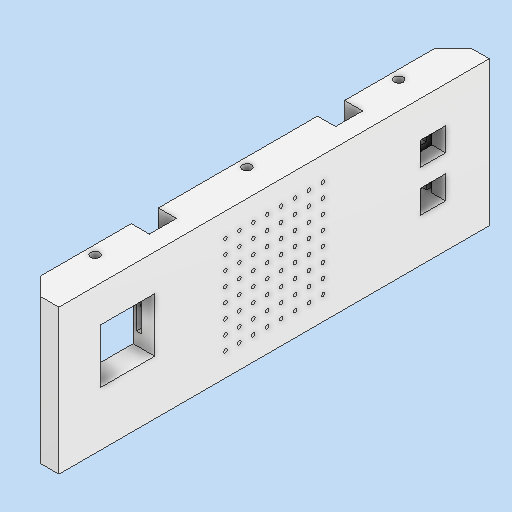
# Autodesk Inventor part: Pared_puertos
Saved by Autodesk Inventor 2027 (Build 310192000, 192)
## iProperties
Created: 2026-11-02
Part Number: Pared_puertos
Material: Plástico PBT
Document SubType Name: Modeling
Designer: alex
Density: 1.31 g/cm^3
Appearance: Suave - Blanco
Author: alex
Autodesk Inventor part; units mm, degrees
ref_plane "YZ Plane" through (0, 0, 0) normal (1, 0, 0) x (0, 1, 0)
ref_plane "XZ Plane" through (0, 0, 0) normal (0, 1, 0) x (-1, 0, 0)
ref_plane "XY Plane" through (0, 0, 0) normal (0, 0, 1) x (1, 0, 0)
sketch "Boceto1" plane through (0, 0, 0) normal (0, 1, 0) x (-1, 0, 0)
  arc A0 (-27.0444, 119.7007) -> (-22.0444, 124.7007) centre (-27.0444, 124.7007) ccw
  circle A1 centre (-27.0444, 124.7007) radius 2.5
  line L0 (-32.0444, 119.7007) -> (-27.0444, 119.7007)
  arc A2 (-27.0444, 119.7007) -> (-22.0444, 124.7007) centre (-27.0444, 124.7007) ccw
  line L1 (-22.0444, 129.7007) -> (-22.0444, 124.7007)
  line L2 (-22.0444, 124.7007) -> (-22.0444, 129.7007)
  line L3 (-22.0444, 129.7007) -> (215.9556, 129.7007)
  line L4 (215.9556, 129.7007) -> (215.9556, 124.7007)
  arc A3 (215.9556, 124.7007) -> (220.9556, 119.7007) centre (220.9556, 124.7007) ccw
  line L5 (225.9556, 119.7007) -> (225.9556, -33.2993)
  line L6 (220.9556, 119.7007) -> (225.9556, 119.7007)
  line L7 (225.9556, -123.2993) -> (225.9556, -118.2993)
  line L8 (225.9556, 119.7007) -> (225.9556, -118.2993)
  line L9 (225.9556, -118.2993) -> (220.9556, -118.2993)
  arc A4 (220.9556, -118.2993) -> (215.9556, -123.2993) centre (220.9556, -123.2993) ccw
  line L10 (-22.0444, -128.2993) -> (215.9556, -128.2993)
  line L11 (215.9556, -123.2993) -> (215.9556, -128.2993)
  line L12 (-22.0444, -128.2993) -> (-22.0444, -123.2993)
  line L13 (215.9556, -128.2993) -> (-22.0444, -128.2993)
  line L14 (-22.0444, -128.2993) -> (-22.0444, -123.2993)
  line L15 (-32.0444, -118.2993) -> (-32.0444, 119.7007)
  arc A5 (220.9556, -118.2993) -> (215.9556, -123.2993) centre (220.9556, -123.2993) ccw
  arc A6 (-22.0444, -123.2993) -> (-27.0444, -118.2993) centre (-27.0444, -123.2993) ccw
  arc A7 (-22.0444, -123.2993) -> (-27.0444, -118.2993) centre (-27.0444, -123.2993) ccw
  line L16 (-27.0444, -118.2993) -> (-32.0444, -118.2993)
  line L17 (-27.0444, -118.2993) -> (-32.0444, -118.2993)
  line L18 (-32.0444, 119.7007) -> (-22.0444, 119.7007)
  line L19 (-22.0444, 119.7007) -> (-22.0444, -118.2993)
  line L20 (-22.0444, -118.2993) -> (-32.0444, -118.2993)
  line L21 (-32.0444, -118.2993) -> (-32.0444, 119.7007)
  line L22 (-22.0444, 119.7007) -> (-12.0444, 119.7007)
  line L23 (-12.0444, 119.7007) -> (-12.0444, 109.7007)
  line L24 (-12.0444, 109.7007) -> (-22.0444, 109.7007)
  line L25 (-22.0444, 109.7007) -> (-22.0444, 119.7007)
  line L26 (-22.0444, -118.2993) -> (-12.0444, -118.2993)
  line L27 (-12.0444, -118.2993) -> (-12.0444, -108.2993)
  line L28 (-12.0444, -108.2993) -> (-22.0444, -108.2993)
  line L29 (-22.0444, -108.2993) -> (-22.0444, -118.2993)
  line L30 (-22.0444, 119.7007) -> (-12.0444, 109.7007)
  line L31 (-12.0444, 109.7007) -> (-22.0444, 109.7007)
  line L32 (-22.0444, 109.7007) -> (-22.0444, 59.7007)
  line L33 (-22.0444, 59.7007) -> (-12.0444, 59.7007)
  line L34 (-12.0444, 59.7007) -> (-12.0444, 109.7007)
  line L35 (-12.0444, -108.2993) -> (-22.0444, -108.2993)
  line L36 (-22.0444, -108.2993) -> (-22.0444, -58.2993)
  line L37 (-22.0444, -58.2993) -> (-12.0444, -58.2993)
  line L38 (-12.0444, -58.2993) -> (-12.0444, -108.2993)
  line L39 (-22.0444, -118.2993) -> (-12.0444, -108.2993)
  line L40 (-22.0444, 44.7007) -> (-12.0444, 44.7007)
  line L41 (-12.0444, 44.7007) -> (-12.0444, -43.2993)
  line L42 (-12.0444, -43.2993) -> (-22.0444, -43.2993)
  line L43 (-22.0444, -43.2993) -> (-22.0444, 44.7007)
  circle A8 centre (-17.0444, 84.7007) radius 2.5
  circle A9 centre (-17.0444, -83.2993) radius 2.5
  circle A10 centre (-17.0444, 0.7007) radius 2.5
  point P0 (0, 0)
  point P1 (-229.0444, 129.7007)
  dimension "d0" = 10
  dimension "d1" = 10
  dimension "d2" = 10
  dimension "d3" = 10
  dimension "d4" = 50
  dimension "d5" = 50
  dimension "d6" = 15
  dimension "d7" = 15
  dimension "d8" = 5
  dimension "d9" = 5
  dimension "d10" = 25
  dimension "d11" = 25
  dimension "d12" = 5
  constraints: 88 end point, 14 point on circle, 13 parallel, 13 perpendicular, 11 centre point, 7 horizontal, 5 point on line, 2 concentric, 1 coincident, 1 collinear, 1 vertical
  measures "d0" distance of L23.end L24.end
  measures "d1" distance of L22.end L23.end
  measures "d2" distance of L28.end L27.end
  measures "d3" distance of L27.end L26.end
  measures "d4" distance of L32.end L31.end
  measures "d5" distance of L35.end L36.end
  measures "d6" distance between parallel lines of L33 L40
  measures "d7" distance between parallel lines of L42 L37
  measures "d8" diameter of A8
  measures "d9" diameter of A9
  measures "d10" distance from line of L33 A8.centre
  measures "d11" distance from line of A9.centre L37
  measures "d12" diameter of A10
extrude "Extrusión1" add sketch "Boceto1" along normal blind 80 contours L18 L19 L20 L16 L15 L0 | L30 L24 L19 | L24 L34 L33 L19 | L19 L28 L39 | L40 L41 L42 L19 | L19 L37 L38 L28
sketch "Boceto2" plane through (32.0444, 0, 119.7007) normal (1, 0, 0) x (0, 0, -1)
  line L0 (23, 60) -> (53, 60)
  line L1 (53, 60) -> (53, 30)
  line L2 (53, 30) -> (23, 30)
  line L3 (23, 30) -> (23, 60)
  line L4 (0, 80) -> (238, 80) projected
  line L5 (0, 0) -> (0, 80) projected
  line L6 (199.856, 60) -> (213.856, 60)
  line L7 (213.856, 60) -> (213.856, 47)
  line L8 (213.856, 47) -> (199.856, 47)
  line L9 (199.856, 47) -> (199.856, 60)
  line L10 (199.856, 37) -> (213.856, 37)
  line L11 (213.856, 37) -> (213.856, 24)
  line L12 (213.856, 24) -> (199.856, 24)
  line L13 (199.856, 24) -> (199.856, 37)
  point P0 (119.7007, 0)
  dimension "d15" = 30
  dimension "d16" = 30
  dimension "d17" = 20
  dimension "d18" = 23
  dimension "d19" = 14
  dimension "d20" = 13
  dimension "d21" = 20
  dimension "d22" = 13
  dimension "d23" = 10
  constraints: 24 end point, 6 parallel, 3 horizontal, 3 perpendicular
  measures "d15" distance of L1.end L2.end
  measures "d16" distance of L0.end L1.end
  measures "d17" distance between parallel lines of L4 L0
  measures "d18" distance between parallel lines of L5 L3
  measures "d19" distance of L7.end L8.end
  measures "d20" distance of L6.end L7.end
  measures "d21" distance between parallel lines of L4 L6
  measures "d22" distance of L10.end L11.end
  measures "d23" distance between parallel lines of L10 L8
extrude "Extrusión2" cut sketch "Boceto2" against normal blind 80
sketch "Boceto3" plane through (12.0444, 0, -108.2993) normal (-1, 0, 0) x (0, 0, 1)
  point P0 (108.2993, 0)
sketch "Boceto4" plane through (12.0444, 0, -108.2993) normal (-1, 0, 0) x (0, 0, 1)
  line L0 (0, 0) -> (0, 80) projected
  line L1 (218, 0) -> (218, 80) projected
  line L2 (0, 70) -> (218, 70)
  line L3 (218, 70) -> (218, 10)
  line L4 (218, 10) -> (0, 10)
  line L5 (0, 10) -> (0, 70)
  line L6 (0, 0) -> (50, 0) projected
  line L7 (0, 80) -> (50, 80) projected
  point P0 (108.2993, 0)
  point P1 (0, 10)
  dimension "d26" = 10
  dimension "d27" = 10
  constraints: 8 end point, 2 parallel, 2 point on line, 1 horizontal, 1 perpendicular
  measures "d26" distance between parallel lines of L6 L4
  measures "d27" distance between parallel lines of L2 L7
extrude "Extrusión3" cut sketch "Boceto4" against normal blind 15
sketch "Boceto5" plane through (27.0444, 0, -108.2993) normal (-1, 0, 0) x (0, 0, 1)
  line L0 (8.144, 65) -> (34.144, 65)
  line L1 (34.144, 65) -> (34.144, 42)
  line L2 (34.144, 42) -> (8.144, 42)
  line L3 (8.144, 42) -> (8.144, 65)
  line L4 (28.144, 47) -> (28.144, 60) projected
  line L5 (14.144, 60) -> (14.144, 47) projected
  line L6 (28.144, 60) -> (14.144, 60) projected
  line L7 (14.144, 47) -> (28.144, 47) projected
  line L8 (8.144, 42) -> (34.144, 42)
  line L9 (34.144, 42) -> (34.144, 19)
  line L10 (34.144, 19) -> (8.144, 19)
  line L11 (8.144, 19) -> (8.144, 42)
  line L12 (28.144, 24) -> (28.144, 37) projected
  line L13 (14.144, 37) -> (14.144, 24) projected
  line L14 (28.144, 37) -> (14.144, 37) projected
  line L15 (14.144, 24) -> (28.144, 24) projected
  circle A0 centre (11.144, 53.5) radius 1.5
  circle A1 centre (11.144, 30.5) radius 1.5
  circle A2 centre (31.144, 30.5) radius 1.5
  circle A3 centre (31.144, 53.5) radius 1.5
  point P0 (108.2993, 0)
  point P1 (21.144, 47)
  point P2 (8.144, 42)
  dimension "d30" = 6
  dimension "d31" = 6
  dimension "d32" = 5
  dimension "d33" = 5
  dimension "d34" = 6
  dimension "d35" = 6
  dimension "d36" = 5
  dimension "d37" = 5
  dimension "d38" = 3
  dimension "d39" = 6.5
  dimension "d40" = 3
  dimension "d41" = 3
  dimension "d42" = 6.5
  dimension "d43" = 3
  dimension "d44" = 3
  dimension "d45" = 3
  constraints: 16 end point, 4 centre point, 4 parallel, 2 coincident, 2 horizontal, 2 perpendicular, 1 midpoint
  measures "d30" distance between parallel lines of L4 L1
  measures "d31" distance between parallel lines of L3 L5
  measures "d32" distance between parallel lines of L6 L0
  measures "d33" distance from line of L2 point (21.144, 47)
  measures "d34" distance between parallel lines of L12 L9
  measures "d35" distance between parallel lines of L11 L13
  measures "d36" distance between parallel lines of L14 L8
  measures "d37" distance between parallel lines of L10 L15
  measures "d38" distance from line of L5 point (11.144, 53.5)
  measures "d39" distance from line of point (11.144, 53.5) L6
  measures "d40" diameter of A0
  measures "d41" distance from line of L4 point (31.144, 53.5)
  measures "d42" distance from line of point (31.144, 53.5) L6
  measures "d43" diameter of A1
  measures "d44" diameter of A2
  measures "d45" diameter of A3
extrude "Extrusión4" add sketch "Boceto5" along normal blind 7.8
sketch "Boceto6" plane through (27.0444, 19, -74.1553) normal (0, 0, 1) x (1, 0, 0)
  line L0 (5, 41) -> (-7.8, 41) projected
  line L1 (5, 5) -> (-7.8, 5) projected
  line L2 (-5.5162, 41) -> (-2.5162, 41)
  line L3 (-2.5162, 41) -> (-2.5162, 5)
  line L4 (-2.5162, 5) -> (-5.5162, 5)
  line L5 (-5.5162, 5) -> (-5.5162, 41)
  point P0 (-27.0444, -19)
  point P1 (-2.5162, 41)
  dimension "d48" = 3
  constraints: 8 end point, 2 parallel, 2 point on line, 1 horizontal, 1 perpendicular
  measures "d48" distance of L3.end L4.end
extrude "Extrusión5" cut sketch "Boceto6" against normal blind 29.7
sketch "Boceto7" plane through (27.0444, 0, -108.2993) normal (-1, 0, 0) x (0, 0, 1)
  line L0 (169, 63.1359) -> (211, 63.1359)
  line L1 (211, 63.1359) -> (211, 25.0492)
  line L2 (211, 25.0492) -> (169, 25.0492)
  line L3 (169, 25.0492) -> (169, 63.1359)
  line L4 (205, 30) -> (205, 60) projected
  line L5 (175, 60) -> (175, 30) projected
  line L6 (171.5, 63) -> (208.5, 63)
  line L7 (208.5, 63) -> (208.5, 28.5687)
  line L8 (208.5, 28.5687) -> (171.5, 28.5687)
  line L9 (171.5, 28.5687) -> (171.5, 63)
  line L10 (208.5, 60) -> (208.5, 48.34)
  line L11 (171.5, 63) -> (171.5, 48.34)
  circle A0 centre (171.5, 48.34) radius 1.5
  circle A1 centre (208.5, 48.34) radius 1.5
  line L12 (171.5, 48.34) -> (171.5, 45.84)
  line L13 (171.5, 48.34) -> (171.5, 50.84)
  line L14 (208.5, 48.34) -> (208.5, 50.84)
  line L15 (208.5, 48.34) -> (208.5, 45.84)
  arc A2 (208.5, 45.84) -> (208.5, 50.84) centre (208.5, 48.34) ccw
  arc A3 (171.5, 50.84) -> (171.5, 45.84) centre (171.5, 48.34) ccw
  line L16 (205, 60) -> (175, 60) projected
  point P0 (108.2993, 0)
  point P1 (190, 63)
  point P2 (190, 60)
  point P3 (208.5, 50.84)
  dimension "d51" = 6
  dimension "d52" = 6
  dimension "d53" = 3.5
  dimension "d54" = 3.5
  dimension "d55" = 11.66
  dimension "d56" = 14.66
  dimension "d57" = 3
  dimension "d58" = 3
  dimension "d59" = 2.5
  dimension "d60" = 2.5
  dimension "d61" = 2.5
  dimension "d62" = 2.5
  dimension "d63" = 3
  constraints: 28 end point, 7 point on line, 4 centre point, 4 parallel, 4 point on circle, 2 coincident, 2 horizontal, 2 midpoint, 2 perpendicular, 2 tangent
  measures "d51" distance between parallel lines of L4 L1
  measures "d52" distance between parallel lines of L3 L5
  measures "d53" distance between parallel lines of L4 L7
  measures "d54" distance between parallel lines of L9 L5
  measures "d55" distance of L10.start L10.end
  measures "d56" distance of L6.start L11.end
  measures "d57" diameter of A0
  measures "d58" diameter of A1
  measures "d59" distance of L12.start L12.end
  measures "d60" distance of L12.start L13.end
  measures "d61" distance of L14.start L14.end
  measures "d62" distance of L14.start L15.end
  measures "d63" distance of point (190, 63) point (190, 60)
extrude "Extrusión6" add sketch "Boceto7" along normal blind 7 contours A3 L9 A0 | A2 L7 A1 | L9 L6 L7 A1 L8 A0
sketch "Boceto8" plane through (20.0444, 0, -108.2993) normal (-1, 0, 0) x (0, 0, 1)
  line L0 (205, 30) -> (205, 60) projected
  line L1 (175, 60) -> (205, 60)
  line L2 (205, 60) -> (205, 30)
  line L3 (205, 30) -> (175, 30)
  line L4 (175, 30) -> (175, 60)
  point P0 (108.2993, 0)
  constraints: 8 end point, 2 parallel, 1 horizontal, 1 perpendicular
extrude "Extrusión7" cut sketch "Boceto8" against normal blind 7
sketch "Boceto9" plane through (27.0444, 50.84, 63.2007) normal (0, 0, -1) x (-1, 0, 0)
  line L0 (2.5588, 4.5741) -> (5.1212, 4.5741)
  line L1 (5.1212, 4.5741) -> (5.1212, -13.7755)
  line L2 (5.1212, -13.7755) -> (2.5588, -13.7755)
  line L3 (2.5588, -13.7755) -> (2.5588, 4.5741)
  point P0 (27.0444, -50.84)
  constraints: 8 end point, 2 parallel, 1 horizontal, 1 perpendicular
extrude "Extrusión8" cut sketch "Boceto9" against normal blind 47
sketch "Boceto10" plane through (32.0444, 30, 96.7007) normal (0, 0, -1) x (-1, 0, 0)
  line L0 (7.5588, 25.4141) -> (10.1212, 25.4141) projected
  line L1 (10.1212, 25.4141) -> (10.1212, 7.0645) projected
  line L2 (7.5588, 25.4141) -> (10.1212, 25.4141)
  line L3 (10.1212, 25.4141) -> (10.1212, 7.0645)
  line L4 (10.1212, 7.0645) -> (7.5588, 7.0645)
  line L5 (7.5588, 7.0645) -> (7.5588, 25.4141)
  point P0 (32.0444, -30)
  constraints: 8 end point, 2 parallel, 1 horizontal, 1 perpendicular
extrude "Extrusión9" cut sketch "Boceto10" along normal blind 47
sketch "Boceto11" plane through (27.0444, 0, -108.2993) normal (-1, 0, 0) x (0, 0, 1)
  line L0 (85, 64) -> (133, 64)
  line L1 (133, 64) -> (133, 16)
  line L2 (133, 16) -> (85, 16)
  line L3 (85, 16) -> (85, 64)
  line L4 (0, 70) -> (218, 70) projected
  line L5 (109, 70) -> (109, 10)
  line L6 (218, 10) -> (0, 10) projected
  line L7 (228, 0) -> (228, 80) projected
  line L8 (228, 40) -> (-10, 40)
  line L9 (-10, 0) -> (-10, 80) projected
  line L10 (88, 61) -> (130, 61)
  line L11 (130, 61) -> (130, 19)
  line L12 (130, 19) -> (88, 19)
  line L13 (88, 19) -> (88, 61)
  point P0 (108.2993, 0)
  dimension "d72" = 48
  dimension "d73" = 48
  dimension "d74" = 24
  dimension "d75" = 24
  dimension "d76" = 3
  dimension "d77" = 3
  dimension "d78" = 3
  dimension "d79" = 3
  constraints: 20 end point, 4 midpoint, 4 parallel, 2 horizontal, 2 perpendicular
  measures "d72" distance of L1.end L2.end
  measures "d73" distance of L0.end L1.end
  measures "d74" distance between parallel lines of L1 L5
  measures "d75" distance between parallel lines of L0 L8
  measures "d76" distance between parallel lines of L10 L0
  measures "d77" distance between parallel lines of L13 L3
  measures "d78" distance between parallel lines of L12 L2
  measures "d79" distance between parallel lines of L11 L1
extrude "Extrusión10" add sketch "Boceto11" along normal blind 10 contours L0 L5 L10 L13 L8 L3 | L0 L1 L8 L11 L10 L5 | L8 L13 L12 L5 L2 L3 | L1 L2 L5 L12 L11 L8
sketch "Boceto12" plane through (17.0444, 0, -108.2993) normal (-1, 0, 0) x (0, 0, 1)
  line L0 (88, 19) -> (88, 61) projected
  circle A0 centre (88, 40) radius 1.5
  line L1 (130, 61) -> (130, 19) projected
  circle A1 centre (130, 40) radius 1.5
  circle A2 centre (88, 40) radius 2
  circle A3 centre (130, 40) radius 2
  point P0 (108.2993, 0)
  point P1 (130, 41.5)
  point P2 (130, 38.5)
  point P3 (88, 41.5)
  point P4 (88, 38.5)
  dimension "d82" = 3
  dimension "d83" = 3
  dimension "d84" = 4
  dimension "d85" = 4
  constraints: 4 centre point, 2 coincident, 2 midpoint
  measures "d82" diameter of A0
  measures "d83" diameter of A1
  measures "d84" diameter of A2
  measures "d85" diameter of A3
extrude "Extrusión11" add sketch "Boceto12" against normal blind 2 contours A2 L0 A0 | L0 A0 A2 | A3 L1 A1 | L1 A1 A3
extrude "Extrusión12" cut sketch "Boceto12" against normal blind 2 contours A0 L0 | A1 L1 picked at (87.8803, 39.5145) picked at (130.5, 40)
sketch "Boceto13" plane through (27.0444, 16, 24.7007) normal (0, 0, 1) x (1, 0, 0)
  line L0 (-8, 19) -> (-5, 19)
  line L1 (-5, 19) -> (-5, 29)
  line L2 (-5, 29) -> (-8, 29)
  line L3 (-8, 29) -> (-8, 19)
  line L4 (-10, 0) -> (-10, 48) projected
  point P0 (-27.0444, -16)
  point P1 (-6.5, 19)
  point P2 (-10, 24)
  dimension "d90" = 3
  dimension "d91" = 10
  dimension "d92" = 5
  constraints: 8 end point, 2 midpoint, 2 parallel, 1 horizontal, 1 perpendicular
  measures "d90" distance of L2.end L1.end
  measures "d91" distance of L1.end L0.end
  measures "d92" vertical distance of point (-6.5, 19) point (-10, 24)
extrude "Extrusión13" cut sketch "Boceto13" against normal blind 57.5
sketch "Boceto14" plane through (32.0444, 0, 119.7007) normal (1, 0, 0) x (0, 0, -1)
  line L0 (146, 13) -> (92, 13)
  line L1 (146, 67) -> (146, 13)
  line L2 (95, 16) -> (143, 16) projected
  line L3 (143, 16) -> (143, 64) projected
  line L4 (95, 64) -> (95, 16) projected
  line L5 (143, 64) -> (95, 64) projected
  circle A0 centre (146, 13) radius 1
  circle A1 centre (146, 20.7) radius 1
  circle A2 centre (146, 28.4) radius 1
  circle A3 centre (146, 36.1) radius 1
  circle A4 centre (146, 43.8) radius 1
  circle A5 centre (146, 51.5) radius 1
  circle A6 centre (146, 59.2) radius 1
  circle A7 centre (146, 66.9) radius 1
  circle A8 centre (138.3, 13) radius 1
  circle A9 centre (138.3, 20.7) radius 1
  circle A10 centre (138.3, 28.4) radius 1
  circle A11 centre (138.3, 36.1) radius 1
  circle A12 centre (138.3, 43.8) radius 1
  circle A13 centre (138.3, 51.5) radius 1
  circle A14 centre (138.3, 59.2) radius 1
  circle A15 centre (138.3, 66.9) radius 1
  circle A16 centre (130.6, 13) radius 1
  circle A17 centre (130.6, 20.7) radius 1
  circle A18 centre (130.6, 28.4) radius 1
  circle A19 centre (130.6, 36.1) radius 1
  circle A20 centre (130.6, 43.8) radius 1
  circle A21 centre (130.6, 51.5) radius 1
  circle A22 centre (130.6, 59.2) radius 1
  circle A23 centre (130.6, 66.9) radius 1
  circle A24 centre (122.9, 13) radius 1
  circle A25 centre (122.9, 20.7) radius 1
  circle A26 centre (122.9, 28.4) radius 1
  circle A27 centre (122.9, 36.1) radius 1
  circle A28 centre (122.9, 43.8) radius 1
  circle A29 centre (122.9, 51.5) radius 1
  circle A30 centre (122.9, 59.2) radius 1
  circle A31 centre (122.9, 66.9) radius 1
  circle A32 centre (115.2, 13) radius 1
  circle A33 centre (115.2, 20.7) radius 1
  circle A34 centre (115.2, 28.4) radius 1
  circle A35 centre (115.2, 36.1) radius 1
  circle A36 centre (115.2, 43.8) radius 1
  circle A37 centre (115.2, 51.5) radius 1
  circle A38 centre (115.2, 59.2) radius 1
  circle A39 centre (115.2, 66.9) radius 1
  circle A40 centre (107.5, 13) radius 1
  circle A41 centre (107.5, 20.7) radius 1
  circle A42 centre (107.5, 28.4) radius 1
  circle A43 centre (107.5, 36.1) radius 1
  circle A44 centre (107.5, 43.8) radius 1
  circle A45 centre (107.5, 51.5) radius 1
  circle A46 centre (107.5, 59.2) radius 1
  circle A47 centre (107.5, 66.9) radius 1
  circle A48 centre (99.8, 13) radius 1
  circle A49 centre (99.8, 20.7) radius 1
  circle A50 centre (99.8, 28.4) radius 1
  circle A51 centre (99.8, 36.1) radius 1
  circle A52 centre (99.8, 43.8) radius 1
  circle A53 centre (99.8, 51.5) radius 1
  circle A54 centre (99.8, 59.2) radius 1
  circle A55 centre (99.8, 66.9) radius 1
  circle A56 centre (92.1, 13) radius 1
  circle A57 centre (92.1, 20.7) radius 1
  circle A58 centre (92.1, 28.4) radius 1
  circle A59 centre (92.1, 36.1) radius 1
  circle A60 centre (92.1, 43.8) radius 1
  circle A61 centre (92.1, 51.5) radius 1
  circle A62 centre (92.1, 59.2) radius 1
  circle A63 centre (92.1, 66.9) radius 1
  point P0 (119.7007, 0)
  point P1 (146, 14)
  point P2 (145, 13)
  dimension "d95" = 3
  dimension "d96" = 3
  dimension "d99" = 2
  dimension "d102" = 7.7
  dimension "d105" = 7.7
  constraints: 64 centre point, 4 end point, 2 horizontal, 1 coincident, 1 vertical, 126 other
  measures "d95" distance between parallel lines of L0 L2
  measures "d96" distance between parallel lines of L1 L3
  measures "d99" diameter of A0
  measures "d102" distance of A0.centre A1.centre
  measures "d105" distance of A0.centre A8.centre
extrude "Extrusión14" cut sketch "Boceto14" against normal blind 5 contours L1 A0 L0 | A56 | A48 L0 | L0 A48 | A40 L0 | L0 A40 | A32 L0 | L0 A32 | A24 L0 | L0 A24 | A16 L0 | L0 A16 | A8 L0 | L0 A8 | A7 | A6 L1 | L1 A6 | A5 L1 | L1 A5 | A4 L1 | L1 A4 | A3 L1 | L1 A3 | A2 L1 | L1 A2 | A1 L1 | L1 A1 | A9 | A10 | A11 | A12 | A13 | A14 | A15 | A17 | A18 | A19 | A20 | A21 | A22 | A23 | A25 | A26 | A27 | A28 | A29 | A30 | A31 | A33 | A34 | A35 | A36 | A37 | A38 | A39 | A41 | A42 | A43 | A44 | A45 | A46 | A47 | A49 | A50 | A51 | A52 | A53 | A54 | A55 | A57 | A58 | A59 | A60 | A61 | A62 | A63 picked at (145.343, 12.9202)
equation "\"d33\" = d32"
equation "\"d36\" = d33"
equation "\"d37\" = d36"
equation "\"d77\" = d76"
equation "\"d78\" = d76"
equation "\"d79\" = d76"
equation "\"d95\" = d96"
